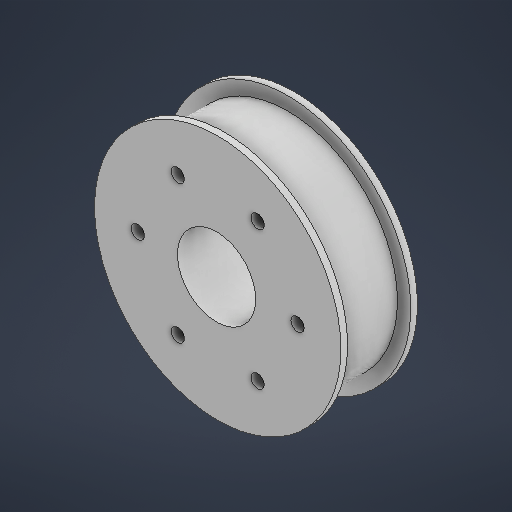
# Autodesk Inventor part: Wheel_Axel
Saved by Autodesk Inventor 2026.2 (Build 302298010, 298A)
## iProperties
Created: 2026-03-26
Part Number: Wheel_Axel
Material: Generic
Document SubType Name: Modeling
Designer: User
Density: 1 g/cm^3
Appearance: Default
Author: User
Autodesk Inventor part; units mm, degrees
ref_plane "YZ Plane" through (0, 0, 0) normal (1, 0, 0) x (0, 1, 0)
ref_plane "XZ Plane" through (0, 0, 0) normal (0, 1, 0) x (-1, 0, 0)
ref_plane "XY Plane" through (0, 0, 0) normal (0, 0, 1) x (1, 0, 0)
sketch "Sketch1" plane through (0, 0, 0) normal (0, 0, 1) x (1, 0, 0)
  circle A0 centre (0, 0) radius 33
  constraints: 2 coincident, 1 centre point
extrude "Extrusion1" add sketch "Sketch1" along normal blind 19
sketch "Sketch4" plane through (0, 0, 19) normal (0, 0, 1) x (1, 0, 0)
  circle A0 centre (0, 0) radius 37
  dimension "d25" = 74
  constraints: 1 centre point, 1 coincident
  measures "d25" diameter of A0
extrude "Extrusion2" add sketch "Sketch4" along normal blind 2
sketch "Sketch5" plane through (0, 0, 0) normal (0, 0, -1) x (-1, 0, 0)
  circle A0 centre (0, 0) radius 37
  dimension "d28" = 74
  constraints: 1 centre point, 1 coincident
  measures "d28" diameter of A0
extrude "Extrusion3" add sketch "Sketch5" along normal blind 2
sketch "Sketch2" plane through (0, 0, 0) normal (0, 0, -1) x (-1, 0, 0)
  point P0 (0, 0)
  point P1 (0.3579, 0.1409)
hole "Hole1" at (-0.3579, 0.1409, 0) direction (0, 0, 1) diameter 23.5 end through all both
sketch "Sketch3" plane through (0, 0, 0) normal (0, 0, -1) x (-1, 0, 0)
  line L0 (0, 0) -> (24, 0)
  line L1 (24, 0) -> (-24, 0)
  line L2 (-24, 0) -> (-12, 20.7846)
  point P0 (12, -20.7846)
  point P1 (-12, -20.7846)
  point P2 (-24, 0)
  point P3 (12, 20.7846)
  dimension "d10" = 24
  dimension "d11" = 48
  dimension "d12" = 24
  dimension "d13" = 60
  constraints: 6 end point, 2 coincident, 1 horizontal, 1 point on line
  measures "d10" distance of L0.start L0.end
  measures "d11" distance of L0.end L1.end
  measures "d12" distance of L1.end L2.end
  measures "d13" angle of L1 L2
hole "Hole2" at (-12, -20.7846, 0) at (12, -20.7846, 0) at (24, 0, 0) at (12, 20.7846, 0) at (-12, 20.7846, 0) at (-24, 0, 0) direction (0, 0, 1) diameter 4 end through all both
body "Solid1"
